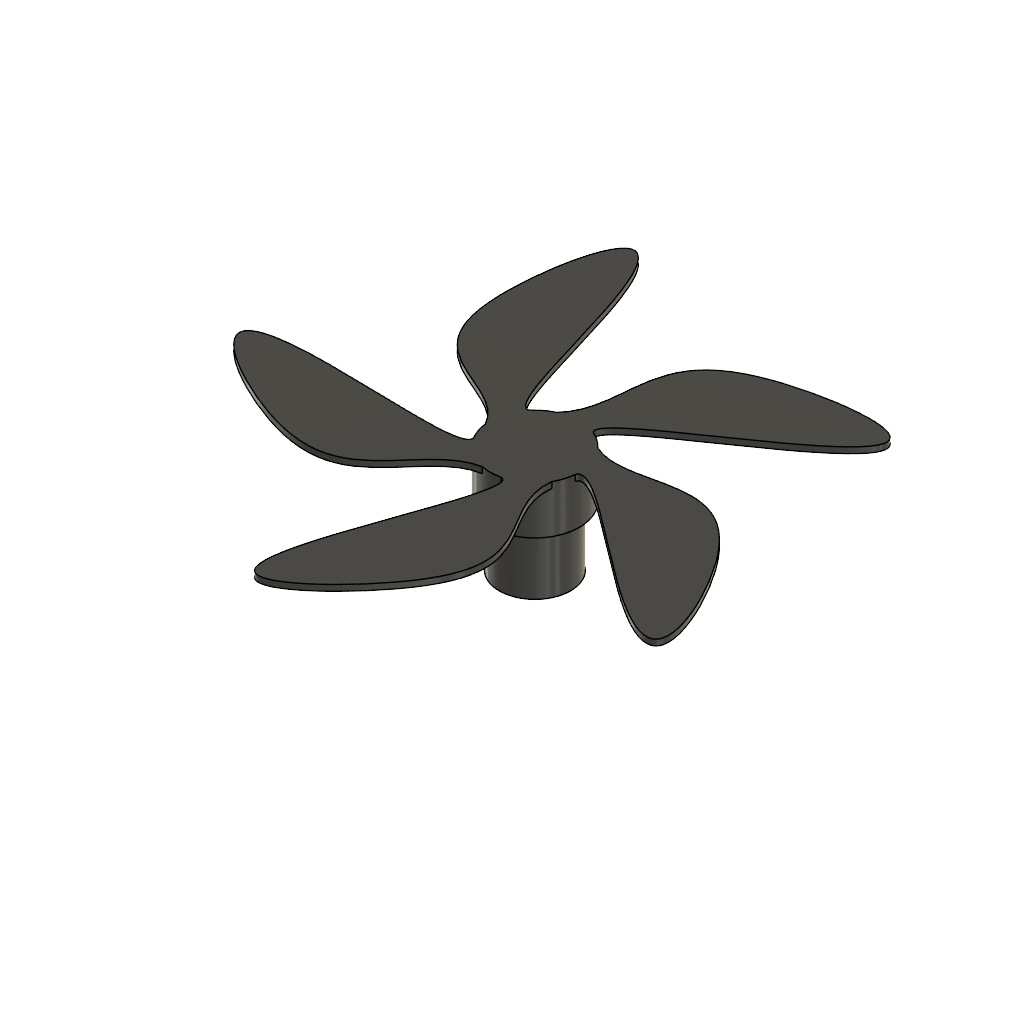
outil_desherbeur (Autodesk Fusion 360 design; units mm, degrees)
part number: 2026-11-26-21-03-43-981
Autodesk Fusion 360 part; units mm, degrees
sketch "Esquisse1" plane through (0, 0, 0) normal (0, 0, 1) x (1, 0, 0)
  circle A0 centre (0, 0) radius 5
  circle A1 centre (0, 0) radius 6
  dimension "d1" = 10
  dimension "d2" = 1
  constraint coincident A0.centre A1.centre
  measures "d1" diameter of A0
extrude "Extrusion1" add sketch "Esquisse1" along normal blind 10
sketch "Esquisse2" plane through (0, 0, 10) normal (0, 0, 1) x (-1, 0, 0)
  circle A0 centre (0, 0) radius 5
  circle A1 centre (0, 0) radius 6
  circle A2 centre (0, 0) radius 7.5
  dimension "d5" = 15
  constraint concentric A0 A2
  measures "d5" diameter of A2
extrude "Extrusion2" add sketch "Esquisse2" along normal blind 8 contours A0 | A1 | A2
sketch "Esquisse3" plane through (0, 0, 18) normal (0, 0, 1) x (-1, 0, 0)
  circle A0 centre (0, 0) radius 7.5
  spline S0 degree 5 poles (-5.5094, -5.0889) (-5.8529, -4.9208) (-6.5664, -4.6305) (-7.7163, -4.333) (-9.4092, -4.2132) (-11.787, -4.4898) (-14.4105, -5.0832) (-17.2424, -5.7614) (-20.2208, -6.1495) (-23.2691, -5.8424) (-26.3152, -4.5128) (-29.2821, -1.9949) (-32.1513, 1.5561) (-34.8127, 5.7221) (-37.0238, 10.0047) (-38.5066, 13.8591) (-38.9904, 16.7861) (-38.2776, 18.3991) (-36.301, 18.5038) (-33.1852, 17.1723) (-29.1946, 14.6759) (-24.6877, 11.4227) (-20.0699, 7.8951) (-15.749, 4.5903) (-12.0883, 1.9579) (-9.3626, 0.3415) (-8.037, -0.0042) (-7.5407, 0.2912) (-7.4306, 0.734) (-7.4307, 1.0168) knots 0 0 0 0 0 0 0.04 0.08 0.12 0.16 0.2 0.24 0.28 0.32 0.36 0.4 0.44 0.48 0.52 0.56 0.6 0.64 0.68 0.72 0.76 0.8 0.84 0.88 0.92 0.96 1 1 1 1 1 1
  line L0 (-27, -4) -> (-31, 0)
  point P0 (-14, -5)
  point P1 (-29, -2)
  point P2 (-38, 18)
  point P3 (-12, 2)
  constraint coincident A0 S0.start
  constraint coincident A0 S0.end
  constraint midpoint P1 L0
extrude "Extrusion3" add sketch "Esquisse3" against normal blind 1 contours A0 S0 picked at (-25.2266, 6.4637)
pattern_circular "Réseau C1" count 5 over 360 about axis through (0, 0, 18) along (0, 0, 1) of "Extrusion3"
